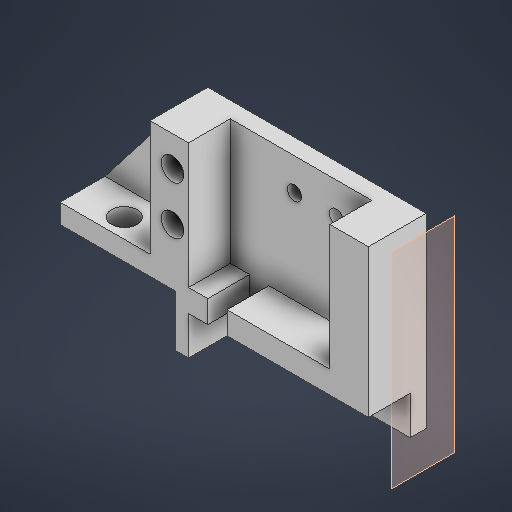
# Autodesk Inventor part: 6_08_support_detectionv
Saved by Autodesk Inventor 2026 (Build 300175000, 175)
## iProperties
Created: 2025-06-19
Part Number: 6_08_support_detectionv
Material: Générique
Document SubType Name: Modeling
Designer: Diogo
Density: 1 g/cm^3
Appearance: Par défaut
Author: Diogo
Autodesk Inventor part; units mm, degrees
ref_plane "YZ Plane" through (0, 0, 0) normal (1, 0, 0) x (0, 1, 0)
ref_plane "XZ Plane" through (0, 0, 0) normal (0, 1, 0) x (-1, 0, 0)
ref_plane "XY Plane" through (0, 0, 0) normal (0, 0, 1) x (1, 0, 0)
sketch "Esquisse1" plane through (0, 0, 0) normal (0, 0, 1) x (1, 0, 0)
  line L0 (18, 0) -> (48, 0)
  line L1 (48, 0) -> (48, 29)
  line L2 (48, 29) -> (14, 29)
  line L3 (0, 8) -> (0, 11)
  line L4 (0, 11) -> (14, 29)
  line L5 (18, 0) -> (18, 8)
  line L6 (18, 8) -> (0, 8)
  line L7 (14, 29) -> (21, 29) construction
  circle A0 centre (17.5, 24.25) radius 1.75
  circle A1 centre (17.5, 16.75) radius 1.75
  circle A2 centre (30, 24) radius 1.1
  circle A3 centre (36.5, 24) radius 1.1
  line L8 (30, 24) -> (41.5236, 24) construction
  point P0 (0, 0)
  point P1 (17.5, 29)
  dimension "d1" = 29
  dimension "d2" = 34
  dimension "d4" = 18
  dimension "d5" = 8
  dimension "d6" = 3
  dimension "d8" = 3.5
  dimension "d9" = 4.75
  dimension "d10" = 3.5
  dimension "d11" = 7.5
  dimension "d12" = 2.2
  dimension "d13" = 9
  dimension "d15" = 5
  dimension "d69" = 6.5
  constraints: 18 end point, 4 centre point, 3 horizontal, 2 perpendicular, 1 equal radius, 1 midpoint, 1 point on line, 1 vertical
  measures "d1" distance of L0.end L1.end
  measures "d2" distance of L1.end L2.end
  measures "d4" distance of L3.start L5.end
  measures "d5" distance of L0.start L5.end
  measures "d6" distance of L3.start L3.end
  measures "d8" diameter of A0
  measures "d9" distance of point (17.5, 29) A0.centre
  measures "d10" diameter of A1
  measures "d11" distance of A0.centre A1.centre
  measures "d12" diameter of A2
  measures "d13" horizontal distance of L8.start L7.end
  measures "d15" distance from line of L2 L8.start
  measures "d69" distance of A3.centre L8.start
extrude "Extrusion1" add sketch "Esquisse1" along normal blind 9
sketch "Esquisse2" plane through (0, 0, 9) normal (0, 0, 1) x (1, 0, 0)
  line L0 (48, 0) -> (48, 29) construction
  line L1 (18, 0) -> (48, 0) construction
  line L2 (18, 8) -> (18, 0) projected
  line L3 (26, 6) -> (26, 9.5)
  line L4 (26, 9.5) -> (42, 9.5)
  line L5 (23, 6) -> (23, 9.5)
  line L6 (23, 9.5) -> (20, 9.5)
  line L7 (23, 6) -> (20, 6)
  line L8 (20, 29) -> (20, 9.5)
  line L9 (20, 6) -> (20, 0)
  line L10 (42, 9.5) -> (42, 29)
  line L11 (42, 29) -> (20, 29)
  line L12 (48, 29) -> (14, 29) projected
  line L13 (26, 6) -> (48, 6)
  line L14 (48, 6) -> (48, 0)
  line L15 (48, 0) -> (20, 0)
  point P0 (0, 0)
  point P1 (48, 11.9654)
  point P2 (21.5, 9.5)
  point P3 (21.5, 6)
  dimension "d72" = 3
  dimension "d73" = 2
  dimension "d74" = 3
  dimension "d75" = 22
  dimension "d77" = 3.5
  dimension "d78" = 6
  constraints: 24 end point, 6 point on line, 5 perpendicular, 4 vertical, 2 midpoint, 1 collinear, 1 horizontal, 1 parallel
  measures "d72" distance between parallel lines of L8 L5
  measures "d73" distance between parallel lines of L2 L8
  measures "d74" distance between parallel lines of L5 L3
  measures "d75" distance between parallel lines of L10 L8
  measures "d77" distance from line of L7 point (21.5, 9.5)
  measures "d78" distance from line of point (21.5, 6) L15
extrude "Extrusion2" cut sketch "Esquisse2" against normal blind 6.5
sketch "Esquisse3" plane through (0, 8, 0) normal (-1, 0, 0) x (0, 0, 1)
  line L0 (0, -8) -> (0, 21) construction
  line L1 (0, 3) -> (9, 3) construction
  line L2 (0, 21) -> (2, 21) construction
  line L3 (2, 21) -> (2, 3) construction
  line L4 (2, 3) -> (0, 3) construction
  line L5 (0, 3) -> (0, 21) construction
  line L6 (0, 21) -> (9, 21) projected
  line L7 (2, 3) -> (9, 3)
  line L8 (9, 3) -> (9, 21)
  line L9 (9, 21) -> (2, 21)
  line L10 (2, 21) -> (2, 3)
  dimension "d29" = 2
  dimension "d30" = 7
  constraints: 16 end point, 4 parallel, 2 horizontal, 2 perpendicular, 2 point on line
  measures "d29" distance of L3.end L4.end
  measures "d30" distance of L9.end L8.end
extrude "Extrusion3" cut sketch "Esquisse3" against normal blind 14
sketch "Esquisse4" plane through (0, 11, 10) normal (0, 1, 0) x (1, 0, 0)
  line L0 (0, 8) -> (0, 1) projected
  line L1 (0, 8) -> (14, 8) projected
  point P0 (0, 10)
  point P1 (7, 4)
  point P2 (0, 0)
  dimension "d33" = 7
  dimension "d41" = 4
  measures "d33" distance from line of L0 point (7, 4)
  measures "d41" distance from line of L1 point (7, 4)
hole "Perçage1" at (7, 11, 6) direction (0, -1, 0) diameter 4 end through all
sketch "Esquisse5" plane through (0, 0, 2.5) normal (0, 0, 1) x (1, 0, 0)
  line L0 (20, 29) -> (42, 29) projected
  line L1 (48, 6) -> (48, 0) projected
  line L2 (48, 0) -> (20, 0) projected
  line L3 (18, 8) -> (18, 0) projected
  point P0 (0, 0)
  point P1 (30, 3)
  point P2 (44.5, 29)
  point P3 (48, 29)
  point P4 (31, 29)
  point P5 (48, 22)
  point P6 (48, 19)
  point P7 (44.75, 29)
  point P8 (48, 26)
  point P9 (44, 29)
  point P10 (44, 0)
  dimension "d70" = 3
  dimension "d71" = 12
  constraints: 1 midpoint
  measures "d70" distance from line of L2 point (30, 3)
  measures "d71" distance from line of L3 point (30, 3)
hole "Perçage2" at (30, 3, 2.5) direction (0, 0, -1) diameter 2.2 end through all
ref_plane "Plan de construction1" through (52, 0, 0) normal (1, 0, 0) x (0, 0, -1)
sketch "Esquisse6" plane through (26, 6, 9) normal (0, -1, 0) x (1, 0, 0)
  line L0 (0, 0) -> (22, 0) projected
  point P0 (-26, -9)
  point P1 (15.8092, -3.25)
  dimension "d86" = 3.25
  measures "d86" distance from line of L0 point (15.809, -3.25)
hole "Perçage3" at (41.8092, 6, 5.75) direction (0, 1, 0) diameter 6 depth 2
